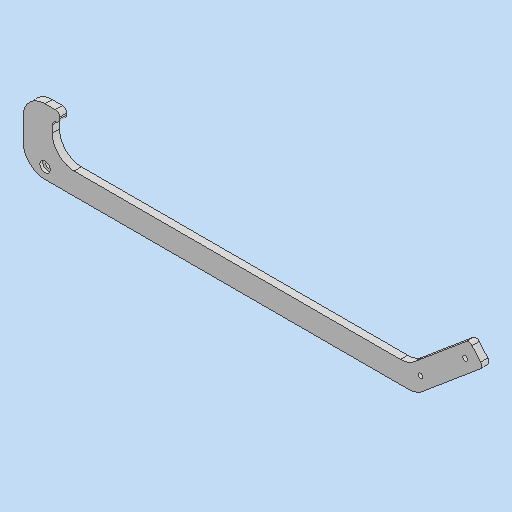
# Autodesk Inventor part: AP5.0_PC-stand1
Saved by Autodesk Inventor 2025.3 (Build 293356030, 356C)
## iProperties
Created: 2025-08-02
Part Number: AP5.0_PC-stand1
Material: 一般
Document SubType Name: Sheet Metal
Designer: ibuki_ono
Density: 1 g/cm^3
Sheet Metal Rule: Default_mm
Appearance: 既定
Author: ibuki_ono
Autodesk Inventor part; units mm, degrees
ref_plane "YZ Plane" through (0, 0, 0) normal (1, 0, 0) x (0, 1, 0)
ref_plane "XZ Plane" through (0, 0, 0) normal (0, 1, 0) x (-1, 0, 0)
ref_plane "XY Plane" through (0, 0, 0) normal (0, 0, 1) x (1, 0, 0)
sketch "スケッチ1" plane through (0, 0, 0) normal (0, 0, 1) x (1, 0, 0)
  line L0 (-125, -7.5) -> (125, -7.5)
  line L1 (125, -7.5) -> (125, 7.5)
  line L2 (125, 7.5) -> (-125, 7.5)
  line L3 (-125, 7.5) -> (-125, -7.5)
  line L4 (-125, -7.5) -> (125, 7.5) construction
  line L5 (125, -7.5) -> (-125, 7.5) construction
  line L6 (125, -7.5) -> (115.3582, 3.9907)
  line L7 (115.3582, 3.9907) -> (161.3209, 42.5579)
  line L8 (161.3209, 42.5579) -> (170.9627, 31.0673)
  line L9 (170.9627, 31.0673) -> (125, -7.5)
  line L10 (125, -7.5) -> (140, -7.5) construction
  line L11 (-125, -7.5) -> (-145, -7.5)
  line L12 (-145, -7.5) -> (-145, 37.5)
  line L13 (-145, 37.5) -> (-125, 37.5)
  line L14 (-125, 37.5) -> (-125, -7.5)
  line L15 (-125, 37.5) -> (-120, 37.5)
  line L16 (-120, 37.5) -> (-120, 30.5)
  line L17 (-120, 30.5) -> (-125, 30.5)
  line L18 (-125, 30.5) -> (-125, 37.5)
  point P0 (0, 0)
  point P1 (119.5404, 7.5)
  point P2 (-125, 7.5)
  dimension "d0" = 250
  dimension "d1" = 15
  dimension "d2" = 15
  dimension "d3" = 130
  dimension "d4" = 60
  dimension "d5" = 20
  dimension "d6" = 45
  dimension "d18" = 5
  dimension "d19" = 7
  measures "d0" distance of L2.end L1.end
  measures "d1" distance of L1.end L0.end
  measures "d2" distance of L0.end L6.end
  measures "d3" angle of L10 L6
  measures "d4" distance of L6.end L7.end
  measures "d5" distance of L12.end L13.end
  measures "d6" distance of L11.end L12.end
  measures "d18" distance of L16.end L17.end
  measures "d19" distance of L15.end L16.end
extrude "プレート1" add sketch "スケッチ1" along normal blind 5
sketch "スケッチ2" plane through (0, 0, 5) normal (0, 0, 1) x (1, 0, 0)
  line L0 (161.3209, 42.5579) -> (170.9627, 31.0673) projected
  line L1 (166.1418, 36.8126) -> (127.8395, 4.6732) construction
  point P0 (0, 0)
  point P1 (158.4813, 30.3847)
  dimension "d8" = 50
  dimension "d9" = 10
  constraints: 2 end point, 1 coincident, 1 midpoint, 1 perpendicular, 1 point on line
  measures "d8" distance of L1.start L1.end
  measures "d9" distance from line of L0 point (158.481, 30.385)
hole "穴1" at (127.8395, 4.6732, 5) at (158.4813, 30.3847, 5) direction (0, 0, -1) diameter 3.1 end through all
fillet "フィレット1" radius 15 3 edges at (-125, 7.5, 2.5) (119.5404, 7.5, 2.5) (125, -7.5, 2.5)
fillet "フィレット2" radius 3 5 edges at (-125, 30.5, 2.5) (-120, 30.5, 2.5) (-120, 37.5, 2.5) (170.9627, 31.0673, 2.5) (161.3209, 42.5579, 2.5)
sketch "スケッチ3" plane through (0, 0, 5) normal (0, 0, 1) x (1, 0, 0)
  line L0 (-145, -7.5) -> (-145, 37.5) projected
  line L1 (-145, 0) -> (-130, 0) construction
  line L2 (-145, 0) -> (-130, 0) construction
  line L3 (119.5404, -7.5) -> (-145, -7.5) construction
  point P0 (0, 0)
  dimension "d22" = 15
  dimension "d23" = 0
  dimension "d24" = 7.5
  constraints: 4 end point, 2 horizontal, 1 coincident, 1 collinear, 1 point on line
  measures "d22" distance of L1.start L1.end
  measures "d23" distance between parallel lines of L1 L2
  measures "d24" distance between parallel lines of L3 L1
hole "穴2" at (-130, 0, 5) direction (0, 0, -1) diameter 3.1 end through all counterbore diameter 7 counterbore depth 2
fillet "フィレット3" radius 15 2 edges at (-145, 37.5, 2.5) (-145, -7.5, 2.5)
equation "\"d15\" = Thickness"
equation "\"d7\" = Thickness"
equation "\"BendRadius\" = Thickness"
equation "\"BendReliefWidth\" = Thickness"
equation "\"BendReliefDepth\" = 0.5 * Thickness"
equation "\"TransitionRadius\" = BendRadius"
equation "\"JacobiRadiusSize\" = BendRadius"
equation "\"GapSize\" = Thickness"
equation "\"Thickness\" = 5"
